Autodesk Fusion 360 part; units mm, degrees
(part 14 of 18)
  line L10793 (174.975, -141.859) -> (174.627, -141.389)
  line L10794 (21.5489, -130.12) -> (21.157, -130.566)
  line L10795 (180.123, -127.511) -> (179.548, -127.659)
  line L10796 (151.541, -210.058) -> (151.739, -210.617)
  line L10797 (186.581, -167.69) -> (187.084, -167.374)
  line L10798 (20.7955, -131.037) -> (20.466, -131.531)
  line L10799 (191.021, -160.387) -> (191.032, -159.95)
  line L10800 (164.561, -215.211) -> (164.044, -215.484)
  line L10801 (188.022, -166.647) -> (188.453, -166.238)
  line L10802 (27.2963, -127.329) -> (26.7068, -127.4)
  line L10803 (119.128, -104.03) -> (119.671, -104.244)
  line L10804 (190.153, -163.819) -> (190.391, -163.276)
  line L10805 (182.046, -168.905) -> (182.639, -168.887)
  line L10806 (109.882, -105.953) -> (110.32, -105.567)
  line L10807 (176.187, -143.121) -> (175.756, -142.727)
  line L10808 (187.565, -167.026) -> (188.022, -166.647)
  line L10809 (188.856, -165.801) -> (189.229, -165.339)
  line L10810 (19.1587, -135.438) -> (19.1245, -136.031)
  line L10811 (182.266, -127.202) -> (182.85, -127.233)
  line L10812 (155.018, -214.739) -> (155.518, -215.058)
  line L10813 (175.549, -130.12) -> (175.157, -130.566)
  line L10814 (186.581, -143.99) -> (187.084, -143.674)
  line L10815 (187.059, -143.805) -> (186.561, -144.111)
  line L10816 (189.229, -165.339) -> (189.57, -164.853)
  line L10817 (173.159, -134.71) -> (173.277, -134.137)
  line L10818 (181.682, -127.209) -> (182.266, -127.202)
  line L10819 (154.539, -214.387) -> (155.018, -214.739)
  line L10820 (166.856, -213.201) -> (167.229, -212.739)
  line L10821 (187.441, -129.079) -> (186.954, -128.74)
  line L10822 (173.909, -132.579) -> (173.683, -133.129)
  line L10823 (189.57, -164.853) -> (189.879, -164.346)
  line L10824 (173.078, -135.288) -> (173.159, -134.71)
  line L10825 (188.938, -130.349) -> (189.304, -130.804)
  line L10826 (154.085, -214.005) -> (154.539, -214.387)
  line L10827 (166.453, -213.638) -> (166.856, -213.201)
  line L10828 (168.389, -210.93) -> (168.14, -211.459)
  line L10829 (184.243, -127.561) -> (183.663, -127.437)
  line L10830 (187.536, -143.468) -> (187.059, -143.805)
  line L10831 (19.1297, -136.625) -> (19.1742, -137.217)
  line L10832 (188.543, -129.918) -> (188.938, -130.349)
  line L10833 (173.777, -139.859) -> (173.562, -139.316)
  line L10834 (36.5439, -133.335) -> (36.3321, -132.78)
  line L10835 (168.602, -210.386) -> (168.389, -210.93)
  line L10836 (190.084, -155.94) -> (189.801, -155.418)
  line L10837 (180.276, -145.022) -> (180.861, -145.122)
  line L10838 (174.55, -141.101) -> (174.888, -141.589)
  line L10839 (188.121, -129.514) -> (188.543, -129.918)
  line L10840 (110.32, -105.567) -> (110.783, -105.21)
  line L10841 (36.7185, -133.902) -> (36.5439, -133.335)
  line L10842 (162.963, -215.927) -> (162.404, -216.096)
  line L10843 (189.801, -155.418) -> (189.483, -154.917)
  line L10844 (177.518, -143.958) -> (178.039, -144.243)
  line L10845 (174.466, -131.531) -> (174.17, -132.046)
  line L10846 (36.8551, -134.48) -> (36.7185, -133.902)
  line L10847 (163.511, -215.723) -> (162.963, -215.927)
  line L10848 (190.391, -163.276) -> (190.594, -162.717)
  line L10849 (185.518, -168.217) -> (186.059, -167.971)
  line L10850 (188.342, -129.852) -> (187.904, -129.451)
  line L10851 (176.417, -129.31) -> (175.97, -129.701)
  line L10852 (158.861, -216.222) -> (159.452, -216.283)
  line L10853 (173.033, -136.031) -> (173.035, -135.871)
  line L10854 (164.044, -215.484) -> (163.511, -215.723)
  line L10855 (190.594, -162.717) -> (190.758, -162.147)
  line L10856 (186.059, -167.971) -> (186.581, -167.69)
  line L10857 (174.727, -130.969) -> (175.084, -130.506)
  line L10858 (184.963, -144.727) -> (185.518, -144.517)
  line L10859 (158.276, -216.122) -> (158.861, -216.222)
  line L10860 (107.622, -109.322) -> (107.848, -108.783)
  line L10861 (177.121, -143.823) -> (176.643, -143.487)
  line L10862 (190.758, -162.147) -> (190.885, -161.567)
  line L10863 (183.816, -168.734) -> (184.395, -168.6)
  line L10864 (174.402, -131.454) -> (174.727, -130.969)
  line L10865 (176.783, -128.91) -> (177.268, -128.584)
  line L10866 (160.639, -216.287) -> (161.23, -216.23)
  line L10867 (107.848, -108.783) -> (108.108, -108.26)
  line L10868 (186.954, -128.74) -> (186.446, -128.433)
  line L10869 (187.99, -143.101) -> (187.536, -143.468)
  line L10870 (184.395, -168.6) -> (184.963, -168.427)
  line L10871 (175.882, -129.653) -> (176.32, -129.267)
  line L10872 (176.32, -129.267) -> (176.783, -128.91)
  line L10873 (160.046, -216.305) -> (160.639, -216.287)
  line L10874 (161.816, -216.134) -> (162.395, -216)
  line L10875 (185.373, -127.924) -> (184.814, -127.724)
  line L10876 (173.683, -133.129) -> (173.495, -133.692)
  line L10877 (184.963, -168.427) -> (185.518, -168.217)
  line L10878 (175.469, -130.066) -> (175.882, -129.653)
  line L10879 (184.005, -127.408) -> (184.571, -127.551)
  line L10880 (159.452, -216.283) -> (160.046, -216.305)
  line L10881 (161.23, -216.23) -> (161.816, -216.134)
  line L10882 (168.218, -203.397) -> (168.456, -203.931)
  line L10883 (117.43, -103.602) -> (118.005, -103.708)
  line L10884 (186.561, -144.111) -> (186.044, -144.384)
  line L10885 (175.084, -130.506) -> (175.469, -130.066)
  line L10886 (183.43, -127.302) -> (184.005, -127.408)
  line L10887 (173.382, -138.76) -> (173.238, -138.193)
  line L10888 (167.879, -211.746) -> (168.153, -211.219)
  line L10889 (167.946, -202.88) -> (168.218, -203.397)
  line L10890 (185.918, -151.861) -> (185.373, -151.624)
  line L10891 (175.257, -142.054) -> (175.657, -142.493)
  line L10892 (182.85, -127.233) -> (183.43, -127.302)
  line L10893 (179.548, -127.659) -> (178.985, -127.846)
  line L10894 (167.57, -212.253) -> (167.879, -211.746)
  line L10895 (167.544, -212.463) -> (167.199, -212.934)
  line L10896 (185.373, -151.624) -> (184.814, -151.424)
  line L10897 (182.046, -145.205) -> (182.639, -145.187)
  line L10898 (176.539, -143.287) -> (177.018, -143.639)
  line L10899 (174.17, -132.046) -> (173.909, -132.579)
  line L10900 (167.229, -212.739) -> (167.57, -212.253)
  line L10901 (167.858, -211.97) -> (167.544, -212.463)
  line L10902 (190.719, -157.602) -> (190.544, -157.035)
  line L10903 (177.018, -167.339) -> (177.518, -167.658)
  line L10904 (190.084, -132.24) -> (189.801, -131.718)
  line L10905 (191.012, -135.657) -> (190.953, -135.066)
  line L10906 (164.581, -215.09) -> (165.084, -214.774)
  line L10907 (173.061, -137.039) -> (173.029, -136.455)
  line L10908 (168.14, -211.459) -> (167.858, -211.97)
  line L10909 (190.544, -157.035) -> (190.332, -156.48)
  line L10910 (177.518, -167.658) -> (178.039, -167.943)
  line L10911 (179.386, -127.609) -> (179.949, -127.454)
  line L10912 (164.059, -215.371) -> (164.581, -215.09)
  line L10913 (108.108, -108.26) -> (108.402, -107.754)
  line L10914 (178.138, -144.398) -> (177.62, -144.127)
  line L10915 (190.332, -156.48) -> (190.084, -155.94)
  line L10916 (175.657, -166.193) -> (176.085, -166.605)
  line L10917 (178.834, -127.801) -> (179.386, -127.609)
  line L10918 (173.432, -133.574) -> (173.622, -133.022)
  line L10919 (166.022, -214.047) -> (166.453, -213.638)
  line L10920 (173.495, -133.692) -> (173.344, -134.266)
  line L10921 (113.949, -103.754) -> (114.521, -103.635)
  line L10922 (188.823, -142.282) -> (188.42, -142.705)
  line L10923 (176.085, -166.605) -> (176.539, -166.987)
  line L10924 (181.099, -127.253) -> (181.682, -127.209)
  line L10925 (173.277, -134.137) -> (173.432, -133.574)
  line L10926 (165.565, -214.426) -> (166.022, -214.047)
  line L10927 (156.039, -215.343) -> (156.578, -215.593)
  line L10928 (112.834, -104.101) -> (113.386, -103.909)
  line L10929 (115.682, -103.509) -> (116.266, -103.502)
  line L10930 (176.539, -166.987) -> (177.018, -167.339)
  line L10931 (180.521, -127.335) -> (181.099, -127.253)
  line L10932 (178.295, -128.028) -> (178.834, -127.801)
  line L10933 (165.084, -214.774) -> (165.565, -214.426)
  line L10934 (155.518, -215.058) -> (156.039, -215.343)
  line L10935 (161.43, -198.402) -> (162.005, -198.508)
  line L10936 (112.295, -104.328) -> (112.834, -104.101)
  line L10937 (184.963, -144.827) -> (184.404, -144.996)
  line L10938 (179.949, -127.454) -> (180.521, -127.335)
  line L10939 (177.772, -128.289) -> (178.295, -128.028)
  line L10940 (173.131, -137.619) -> (173.061, -137.039)
  line L10941 (163.518, -215.617) -> (164.059, -215.371)
  line L10942 (160.85, -198.333) -> (161.43, -198.402)
  line L10943 (180.123, -151.211) -> (179.548, -151.359)
  line L10944 (189.879, -140.646) -> (190.153, -140.119)
  line L10945 (176.085, -142.905) -> (176.539, -143.287)
  line L10946 (177.268, -128.584) -> (177.772, -128.289)
  line L10947 (110.783, -105.21) -> (111.268, -104.884)
  line L10948 (162.963, -215.827) -> (163.518, -215.617)
  line L10949 (168.827, -205.038) -> (168.957, -205.608)
  line L10950 (179.548, -151.359) -> (178.985, -151.546)
  line L10951 (183.816, -145.034) -> (184.395, -144.9)
  line L10952 (178.434, -128.069) -> (177.9, -128.329)
  line L10953 (175.657, -142.493) -> (176.085, -142.905)
  line L10954 (111.268, -104.884) -> (111.772, -104.589)
  line L10955 (162.395, -216) -> (162.963, -215.827)
  line L10956 (168.659, -204.478) -> (168.827, -205.038)
  line L10957 (187.441, -152.779) -> (186.954, -152.44)
  line L10958 (151.848, -203.583) -> (152.108, -203.06)
  line L10959 (176.889, -128.951) -> (176.417, -129.31)
  line L10960 (168.391, -210.676) -> (168.594, -210.117)
  line L10961 (173.238, -138.193) -> (173.131, -137.619)
  line L10962 (168.456, -203.931) -> (168.659, -204.478)
  line L10963 (186.954, -152.44) -> (186.446, -152.133)
  line L10964 (151.622, -204.122) -> (151.848, -203.583)
  line L10965 (185.128, -127.73) -> (185.671, -127.944)
  line L10966 (108.727, -107.269) -> (109.084, -106.806)
  line L10967 (168.153, -211.219) -> (168.391, -210.676)
  line L10968 (175.157, -130.566) -> (174.795, -131.037)
  line L10969 (179.22, -144.837) -> (178.672, -144.635)
  line L10970 (186.446, -152.133) -> (185.918, -151.861)
  line L10971 (152.727, -202.069) -> (153.084, -201.606)
  line L10972 (184.571, -127.551) -> (185.128, -127.73)
  line L10973 (19.6834, -133.129) -> (19.495, -133.692)
  line L10974 (37.0318, -136.25) -> (37.0121, -135.657)
  line L10975 (108.402, -107.754) -> (108.727, -107.269)
  line L10976 (116.266, -103.502) -> (116.85, -103.533)
  line L10977 (189.544, -141.363) -> (189.199, -141.834)
  line L10978 (152.402, -202.554) -> (152.727, -202.069)
  line L10979 (186.711, -128.476) -> (187.203, -128.792)
  line L10980 (19.9088, -132.579) -> (19.6834, -133.129)
  line L10981 (19.6834, -62.0285) -> (19.495, -62.5917)
  line L10982 (151.974, -211.163) -> (152.245, -211.691)
  line L10983 (185.918, -128.161) -> (185.373, -127.924)
  line L10984 (152.108, -203.06) -> (152.402, -202.554)
  line L10985 (186.199, -128.194) -> (186.711, -128.476)
  line L10986 (174.108, -131.96) -> (174.402, -131.454)
  line L10987 (168.594, -210.117) -> (168.758, -209.547)
  line L10988 (151.739, -210.617) -> (151.974, -211.163)
  line L10989 (153.469, -201.166) -> (153.882, -200.753)
  line L10990 (188.022, -142.947) -> (188.453, -142.538)
  line L10991 (183.258, -145.223) -> (182.677, -145.28)
  line L10992 (185.671, -127.944) -> (186.199, -128.194)
  line L10993 (173.848, -132.483) -> (174.108, -131.96)
  line L10994 (173.029, -136.455) -> (173.033, -136.031)
  line L10995 (157.699, -215.983) -> (158.276, -216.122)
  line L10996 (153.084, -201.606) -> (153.469, -201.166)
  line L10997 (178.985, -151.546) -> (178.434, -151.769)
  line L10998 (187.565, -143.326) -> (188.022, -142.947)
  line L10999 (177.018, -143.639) -> (177.518, -143.958)
  line L11000 (173.622, -133.022) -> (173.848, -132.483)
  line L11001 (120.199, -104.494) -> (120.711, -104.776)
  line L11002 (157.132, -215.807) -> (157.699, -215.983)
  line L11003 (163.128, -198.83) -> (163.671, -199.044)
  line L11004 (178.434, -151.769) -> (177.9, -152.029)
  line L11005 (187.084, -143.674) -> (187.565, -143.326)
  line L11006 (183.23, -145.13) -> (183.816, -145.034)
  line L11007 (174.888, -141.589) -> (175.257, -142.054)
  line L11008 (118.571, -103.851) -> (119.128, -104.03)
  line L11009 (156.578, -215.593) -> (157.132, -215.807)
  line L11010 (162.571, -198.651) -> (163.128, -198.83)
  line L11011 (181.889, -150.997) -> (181.296, -151.029)
  line L11012 (158.521, -198.435) -> (159.099, -198.353)
  line L11013 (188.856, -142.101) -> (189.229, -141.639)
  line L11014 (36.084, -132.24) -> (35.8006, -131.718)
  line L11015 (173.562, -139.316) -> (173.382, -138.76)
  line L11016 (162.005, -198.508) -> (162.571, -198.651)
  line L11017 (181.296, -151.029) -> (180.707, -151.1)
  line L11018 (157.949, -198.554) -> (158.521, -198.435)
  line L11019 (189.641, -131.281) -> (189.946, -131.78)
  line L11020 (190.544, -133.335) -> (190.332, -132.78)
  line L11021 (36.3321, -132.78) -> (36.084, -132.24)
  line L11022 (180.927, -145.227) -> (180.35, -145.134)
  line L11023 (180.707, -151.1) -> (180.123, -151.211)
  line L11024 (160.266, -198.302) -> (160.85, -198.333)
  line L11025 (189.304, -130.804) -> (189.641, -131.281)
  line L11026 (23.3845, -128.623) -> (22.8893, -128.951)
  line L11027 (35.1334, -130.737) -> (34.7525, -130.281)
  line L11028 (186.446, -128.433) -> (185.918, -128.161)
  line L11029 (190.14, -140.359) -> (189.858, -140.87)
  line L11030 (159.682, -198.309) -> (160.266, -198.302)
  line L11031 (190.456, -132.831) -> (190.659, -133.378)
  line L11032 (23.9003, -128.329) -> (23.3845, -128.623)
  line L11033 (35.4833, -131.217) -> (35.1334, -130.737)
  line L11034 (151.131, -208.719) -> (151.061, -208.139)
  line L11035 (173.232, -134.849) -> (173.159, -135.438)
  line L11036 (116.85, -103.533) -> (117.43, -103.602)
  line L11037 (159.099, -198.353) -> (159.682, -198.309)
  line L11038 (35.8006, -131.718) -> (35.4833, -131.217)
  line L11039 (190.218, -132.297) -> (190.456, -132.831)
  line L11040 (19.232, -134.849) -> (19.1587, -135.438)
  line L11041 (174.888, -165.289) -> (175.257, -165.754)
  line L11042 (115.099, -103.553) -> (115.682, -103.509)
  line L11043 (151.238, -209.293) -> (151.131, -208.719)
  line L11044 (181.509, -145.282) -> (180.927, -145.227)
  line L11045 (189.946, -131.78) -> (190.218, -132.297)
  line L11046 (19.3443, -134.266) -> (19.232, -134.849)
  line L11047 (173.035, -135.871) -> (173.078, -135.288)
  line L11048 (152.888, -212.689) -> (153.257, -213.154)
  line L11049 (175.257, -165.754) -> (175.657, -166.193)
  line L11050 (183.075, -151.051) -> (182.483, -151.004)
  line L11051 (181.452, -145.183) -> (182.046, -145.205)
  line L11052 (178.039, -144.243) -> (178.578, -144.493)
  line L11053 (19.495, -133.692) -> (19.3443, -134.266)
  line L11054 (189.229, -141.639) -> (189.57, -141.153)
  line L11055 (152.55, -212.201) -> (152.888, -212.689)
  line L11056 (154.783, -200.01) -> (155.268, -199.684)
  line L11057 (182.483, -151.004) -> (181.889, -150.997)
  line L11058 (189.57, -141.153) -> (189.879, -140.646)
  line L11059 (177.9, -128.329) -> (177.385, -128.623)
  line L11060 (174.245, -140.591) -> (174.55, -141.101)
  line L11061 (111.772, -104.589) -> (112.295, -104.328)
  line L11062 (152.245, -211.691) -> (152.55, -212.201)
  line L11063 (154.32, -200.367) -> (154.783, -200.01)
  line L11064 (184.814, -151.424) -> (184.243, -151.261)
  line L11065 (166.543, -201.018) -> (166.938, -201.449)
  line L11066 (177.385, -128.623) -> (176.889, -128.951)
  line L11067 (190.332, -132.78) -> (190.084, -132.24)
  line L11068 (31.9179, -128.161) -> (31.3734, -127.924)
  line L11069 (174.028, -140.387) -> (173.777, -139.859)
  line L11070 (153.882, -200.753) -> (154.32, -200.367)
  line L11071 (184.243, -151.261) -> (183.663, -151.137)
  line L11072 (166.121, -200.614) -> (166.543, -201.018)
  line L11073 (188.753, -130.281) -> (188.342, -129.852)
  line L11074 (109.084, -106.806) -> (109.469, -106.366)
  line L11075 (32.4456, -128.433) -> (31.9179, -128.161)
  line L11076 (173.344, -134.266) -> (173.232, -134.849)
  line L11077 (182.677, -145.28) -> (182.093, -145.3)
  line L11078 (183.663, -151.137) -> (183.075, -151.051)
  line L11079 (167.641, -202.381) -> (167.946, -202.88)
  line L11080 (184.395, -144.9) -> (184.963, -144.727)
  line L11081 (29.075, -127.351) -> (28.483, -127.304)
  line L11082 (30.2432, -127.561) -> (29.6626, -127.437)
  line L11083 (114.521, -103.635) -> (115.099, -103.553)
  line L11084 (189.858, -140.87) -> (189.544, -141.363)
  line L11085 (167.304, -201.904) -> (167.641, -202.381)
  line L11086 (190.922, -138.162) -> (190.781, -138.729)
  line L11087 (29.6626, -127.437) -> (29.075, -127.351)
  line L11088 (30.8143, -127.724) -> (30.2432, -127.561)
  line L11089 (153.756, -213.827) -> (153.351, -213.406)
  line L11090 (173.159, -135.438) -> (173.124, -136.031)
  line L11091 (180.861, -145.122) -> (181.452, -145.183)
  line L11092 (166.938, -201.449) -> (167.304, -201.904)
  line L11093 (191.027, -137.588) -> (190.922, -138.162)
  line L11094 (21.9695, -129.701) -> (21.5489, -130.12)
  line L11095 (31.3734, -127.924) -> (30.8143, -127.724)
  line L11096 (154.187, -214.221) -> (153.756, -213.827)
  line L11097 (182.639, -168.887) -> (183.23, -168.83)
  line L11098 (186.059, -144.271) -> (186.581, -143.99)
  line L11099 (179.78, -145.004) -> (179.22, -144.837)
  line L11100 (191.095, -137.007) -> (191.027, -137.588)
  line L11101 (22.417, -129.31) -> (21.9695, -129.701)
  line L11102 (173.258, -137.805) -> (173.38, -138.386)
  line L11103 (151.033, -207.131) -> (151.035, -206.971)
  line L11104 (183.23, -168.83) -> (183.816, -168.734)
  line L11105 (188.342, -153.552) -> (187.904, -153.151)
  line L11106 (179.132, -144.707) -> (179.699, -144.883)
  line L11107 (22.8893, -128.951) -> (22.417, -129.31)
  line L11108 (151.029, -207.555) -> (151.033, -207.131)
  line L11109 (173.974, -163.763) -> (174.245, -164.291)
  line L11110 (187.904, -153.151) -> (187.441, -152.779)
  line L11111 (190.885, -137.867) -> (190.972, -137.279)
  line L11112 (191.051, -135.084) -> (191.108, -135.666)
  line L11113 (173.739, -139.517) -> (173.974, -140.063)
  line L11114 (119.671, -104.244) -> (120.199, -104.494)
  line L11115 (151.061, -208.139) -> (151.029, -207.555)
  line L11116 (174.245, -164.291) -> (174.55, -164.801)
  line L11117 (189.483, -154.917) -> (189.133, -154.437)
  line L11118 (169.027, -208.688) -> (168.922, -209.262)
  line L11119 (190.957, -134.508) -> (191.051, -135.084)
  line L11120 (109.469, -106.366) -> (109.882, -105.953)
  line L11121 (26.1233, -127.511) -> (25.5484, -127.659)
  line L11122 (174.627, -141.389) -> (174.311, -140.898)
  line L11123 (174.55, -164.801) -> (174.888, -165.289)
  line L11124 (189.133, -154.437) -> (188.753, -153.981)
  line L11125 (169.095, -208.107) -> (169.027, -208.688)
  line L11126 (190.827, -133.938) -> (190.957, -134.508)
  line L11127 (191.032, -136.25) -> (191.012, -135.657)
  line L11128 (26.7068, -127.4) -> (26.1233, -127.511)
  line L11129 (190.719, -133.902) -> (190.544, -133.335)
  line L11130 (184.404, -144.996) -> (183.835, -145.128)
  line L11131 (188.753, -153.981) -> (188.342, -153.552)
  line L11132 (168.781, -209.829) -> (168.602, -210.386)
  line L11133 (190.659, -133.378) -> (190.827, -133.938)
  line L11134 (34.3423, -129.852) -> (33.9045, -129.451)
  line L11135 (24.4345, -128.069) -> (23.9003, -128.329)
  line L11136 (190.855, -134.48) -> (190.719, -133.902)
  line L11137 (173.124, -136.031) -> (173.13, -136.625)
  line L11138 (189.199, -141.834) -> (188.823, -142.282)
  line L11139 (168.922, -209.262) -> (168.781, -209.829)
  line L11140 (190.389, -139.83) -> (190.14, -140.359)
  line L11141 (34.7525, -130.281) -> (34.3423, -129.852)
  line L11142 (24.9847, -127.846) -> (24.4345, -128.069)
  line L11143 (158.927, -216.327) -> (158.35, -216.234)
  line L11144 (173.13, -136.625) -> (173.174, -137.217)
  line L11145 (94.6766, -97.8801) -> (94.0926, -97.9)
  line L11146 (95.2302, -97.7304) -> (95.8162, -97.6345)
  line L11147 (103.027, -90.1877) -> (102.922, -90.7625)
  line L11148 (115.099, -79.8529) -> (115.682, -79.8086)
  line L11149 (120.711, -81.0764) -> (121.203, -81.3917)
  line L11150 (85.495, -86.2917) -> (85.3443, -86.866)
  line L11151 (93.2963, -79.9291) -> (92.7068, -80.0004)
  line L11152 (89.1214, -96.4227) -> (88.643, -96.0871)
  line L11153 (85.0347, -88.471) -> (85.078, -87.8883)
  line L11154 (88.539, -95.8873) -> (89.0175, -96.2389)
  line L11155 (93.0994, -79.8529) -> (93.682, -79.8086)
  line L11156 (95.8162, -97.6345) -> (96.3945, -97.4999)
  line L11157 (89.0175, -96.2389) -> (89.5183, -96.5579)
  line L11158 (91.7803, -97.6038) -> (91.2202, -97.4373)
  line L11159 (85.1742, -89.8171) -> (85.2578, -90.405)
  line L11160 (85.5618, -91.9156) -> (85.3817, -91.3597)
  line L11161 (102.594, -91.6172) -> (102.758, -91.0467)
  line L11162 (36.8551, -110.78) -> (36.7185, -110.202)
  line L11163 (124.456, -85.4305) -> (124.659, -85.9784)
  line L11164 (102.827, -86.5382) -> (102.957, -87.1077)
  line L11165 (89.5183, -96.5579) -> (90.0392, -96.8431)
  line L11166 (19.1297, -112.925) -> (19.1742, -113.517)
  line L11167 (36.3914, -115.876) -> (36.5935, -115.317)
  line L11168 (95.8346, -97.7276) -> (95.2581, -97.8226)
  line L11169 (88.1873, -95.7214) -> (87.7561, -95.327)
  line L11170 (102.084, -84.8403) -> (101.801, -84.3185)
  line L11171 (86.6274, -93.989) -> (86.3113, -93.4975)
  line L11172 (25.5484, -103.959) -> (24.9847, -104.146)
  line L11173 (119.671, -80.5443) -> (120.199, -80.7936)
  line L11174 (19.1245, -112.331) -> (19.1297, -112.925)
  line L11175 (100.121, -82.114) -> (100.543, -82.518)
  line L11176 (36.5439, -109.635) -> (36.3321, -109.08)
  line L11177 (85.0291, -89.0553) -> (85.0332, -88.6312)
  line L11178 (88.7829, -81.5099) -> (89.2676, -81.1835)
  line L11179 (121.203, -81.3917) -> (121.673, -81.738)
  line L11180 (102.544, -85.9345) -> (102.332, -85.3798)
  line L11181 (121.673, -81.738) -> (122.121, -82.114)
  line L11182 (93.5085, -97.8821) -> (92.9269, -97.8266)
  line L11183 (87.157, -83.166) -> (86.7955, -83.6371)
  line L11184 (97.5109, -97.2231) -> (96.9634, -97.4273)
  line L11185 (85.2379, -90.7934) -> (85.1309, -90.2189)
  line L11186 (103.108, -88.266) -> (103.127, -88.85)
  line L11187 (88.417, -81.9104) -> (87.9695, -82.3007)
  line L11188 (112.834, -80.4011) -> (113.386, -80.2094)
  line L11189 (86.3113, -93.4975) -> (86.0276, -92.9867)
  line L11190 (92.1233, -80.1107) -> (91.5484, -80.2593)
  line L11191 (122.543, -82.518) -> (122.938, -82.9485)
  line L11192 (27.2963, -103.629) -> (26.7068, -103.7)
  line L11193 (88.3203, -81.8668) -> (88.7829, -81.5099)
  line L11194 (98.0585, -96.8711) -> (98.5813, -96.5896)
  line L11195 (119.128, -80.3297) -> (119.671, -80.5443)
  line L11196 (113.949, -80.0538) -> (114.521, -79.9348)
  line L11197 (37.0121, -111.957) -> (36.9531, -111.366)
  line L11198 (101.133, -83.3368) -> (100.753, -82.8812)
  line L11199 (23.9003, -104.629) -> (23.3845, -104.923)
  line L11200 (92.5208, -79.9348) -> (93.0994, -79.8529)
  line L11201 (100.453, -95.1378) -> (100.856, -94.7014)
  line L11202 (118.571, -80.1506) -> (119.128, -80.3297)
  line L11203 (91.6987, -97.4835) -> (92.2761, -97.6221)
  line L11204 (31.9179, -104.461) -> (31.3734, -104.224)
  line L11205 (125.108, -88.266) -> (125.127, -88.85)
  line L11206 (101.641, -83.8813) -> (101.946, -84.3798)
  line L11207 (90.4345, -80.6692) -> (89.9003, -80.9286)
  line L11208 (20.466, -107.831) -> (20.17, -108.346)
  line L11209 (27.8893, -103.597) -> (27.2963, -103.629)
  line L11210 (36.7582, -114.747) -> (36.8847, -114.167)
  line L11211 (94.6391, -97.7873) -> (95.2302, -97.7304)
  line L11212 (85.6834, -85.7285) -> (85.495, -86.2917)
  line L11213 (29.6626, -103.737) -> (29.075, -103.651)
  line L11214 (101.946, -84.3798) -> (102.218, -84.8969)
  line L11215 (102.758, -91.0467) -> (102.885, -90.4665)
  line L11216 (21.9695, -106.001) -> (21.5489, -106.42)
  line L11217 (91.5484, -80.2593) -> (90.9847, -80.4458)
  line L11218 (90.138, -96.9979) -> (89.6204, -96.7267)
  line L11219 (97.3734, -80.5239) -> (96.8143, -80.3237)
  line L11220 (30.8143, -104.024) -> (30.2432, -103.861)
  line L11221 (115.682, -79.8086) -> (116.266, -79.802)
  line L11222 (98.1995, -80.7936) -> (98.7108, -81.0764)
  line L11223 (102.957, -87.1077) -> (103.051, -87.6844)
  line L11224 (102.391, -92.1756) -> (102.594, -91.6172)
  line L11225 (85.3443, -86.866) -> (85.2321, -87.4491)
  line L11226 (102.972, -89.8793) -> (103.021, -89.2874)
  line L11227 (35.4833, -107.517) -> (35.1334, -107.037)
  line L11228 (96.9627, -97.3272) -> (97.5182, -97.1173)
  line L11229 (87.8816, -82.2528) -> (88.3203, -81.8668)
  line L11230 (21.5489, -106.42) -> (21.157, -106.866)
  line L11231 (30.2432, -103.861) -> (29.6626, -103.737)
  line L11232 (86.1085, -84.5595) -> (86.402, -84.0542)
  line L11233 (103.125, -89.0237) -> (103.095, -89.6073)
  line L11234 (90.672, -97.2351) -> (90.138, -96.9979)
  line L11235 (95.2581, -97.8226) -> (94.6766, -97.8801)
  line L11236 (101.304, -83.4036) -> (101.641, -83.8813)
  line L11237 (102.922, -90.7625) -> (102.781, -91.3293)
  line L11238 (98.954, -81.3397) -> (98.4456, -81.033)
  line L11239 (36.9725, -113.579) -> (37.0211, -112.987)
  line L11240 (111.772, -80.8892) -> (112.295, -80.628)
  line L11241 (86.2446, -93.1915) -> (86.5495, -93.701)
  line L11242 (96.8143, -80.3237) -> (96.2432, -80.161)
  line L11243 (107.848, -85.0827) -> (108.108, -84.5595)
  line L11244 (32.4456, -104.733) -> (31.9179, -104.461)
  line L11245 (98.4456, -81.033) -> (97.9179, -80.7606)
  line L11246 (87.2572, -94.6539) -> (87.6569, -95.0931)
  line L11247 (94.8498, -79.8331) -> (95.4301, -79.9018)
  line L11248 (124.218, -84.8969) -> (124.456, -85.4305)
  line L11249 (94.483, -79.9042) -> (93.8893, -79.897)
  line L11250 (95.075, -79.9508) -> (94.483, -79.9042)
  line L11251 (101.879, -93.246) -> (102.153, -92.7193)
  line L11252 (86.402, -84.0542) -> (86.7274, -83.569)
  line L11253 (94.0926, -97.9) -> (93.5085, -97.8821)
  line L11254 (100.753, -82.8812) -> (100.342, -82.4519)
  line L11255 (107.159, -87.3096) -> (107.277, -86.7373)
  line L11256 (86.7274, -83.569) -> (87.0836, -83.1057)
  line L11257 (107.078, -87.8883) -> (107.159, -87.3096)
  line L11258 (96.0047, -80.0077) -> (96.5713, -80.1506)
  line L11259 (100.022, -95.5465) -> (100.453, -95.1378)
  line L11260 (85.1587, -88.0384) -> (85.1245, -88.6312)
  line L11261 (101.544, -93.963) -> (101.199, -94.4342)
  line L11262 (100.938, -82.9485) -> (101.304, -83.4036)
  line L11263 (102.389, -92.4297) -> (102.14, -92.9586)
  line L11264 (92.9269, -97.8266) -> (92.35, -97.7337)
  line L11265 (91.9488, -80.0538) -> (92.5208, -79.9348)
  line L11266 (36.084, -108.54) -> (35.8006, -108.018)
  line L11267 (85.1297, -89.225) -> (85.1742, -89.8171)
  line L11268 (24.9847, -104.146) -> (24.4345, -104.369)
  line L11269 (29.075, -103.651) -> (28.483, -103.604)
  line L11270 (114.521, -79.9348) -> (115.099, -79.8529)
  line L11271 (86.8876, -94.1892) -> (87.2572, -94.6539)
  line L11272 (20.7955, -107.337) -> (20.466, -107.831)
  line L11273 (86.0276, -92.9867) -> (85.7774, -92.4587)
  line L11274 (90.0392, -96.8431) -> (90.5778, -97.0931)
  line L11275 (86.7955, -83.6371) -> (86.466, -84.1311)
  line L11276 (31.3734, -104.224) -> (30.8143, -104.024)
  line L11277 (102.332, -85.3798) -> (102.084, -84.8403)
  line L11278 (103.095, -89.6073) -> (103.027, -90.1877)
  line L11279 (102.885, -90.4665) -> (102.972, -89.8793)
  line L11280 (102.153, -92.7193) -> (102.391, -92.1756)
  line L11281 (123.946, -84.3798) -> (124.218, -84.8969)
  line L11282 (107.432, -86.1738) -> (107.622, -85.6215)
  line L11283 (35.8785, -116.946) -> (36.1527, -116.419)
  line L11284 (85.1309, -90.2189) -> (85.0612, -89.6388)
  line L11285 (102.719, -86.5021) -> (102.544, -85.9345)
  line L11286 (87.3513, -94.9056) -> (86.9746, -94.459)
  line L11287 (87.5489, -82.7199) -> (87.157, -83.166)
  line L11288 (88.8893, -81.5505) -> (88.417, -81.9104)
  line L11289 (102.659, -85.9784) -> (102.827, -86.5382)
  line L11290 (122.938, -82.9485) -> (123.304, -83.4036)
  line L11291 (103.051, -87.6844) -> (103.108, -88.266)
  line L11292 (98.5813, -96.5896) -> (99.0844, -96.274)
  line L11293 (95.4301, -79.9018) -> (96.0047, -80.0077)
  line L11294 (101.801, -84.3185) -> (101.483, -83.8165)
  line L11295 (34.7525, -106.581) -> (34.3423, -106.152)
  line L11296 (19.1587, -111.738) -> (19.1245, -112.331)
  line L11297 (91.2202, -97.4373) -> (90.672, -97.2351)
  line L11298 (112.295, -80.628) -> (112.834, -80.4011)
  line L11299 (35.57, -117.453) -> (35.8785, -116.946)
  line L11300 (99.2028, -81.3917) -> (99.6734, -81.738)
  line L11301 (99.6734, -81.738) -> (100.121, -82.114)
  line L11302 (124.827, -86.5382) -> (124.957, -87.1077)
  line L11303 (86.9746, -94.459) -> (86.6274, -93.989)
  line L11304 (99.0587, -96.4054) -> (98.5607, -96.7111)
  line L11305 (109.469, -82.6664) -> (109.882, -82.2528)
  line L11306 (102.14, -92.9586) -> (101.858, -93.4704)
  line L11307 (23.3845, -104.923) -> (22.8893, -105.251)
  line L11308 (96.5713, -80.1506) -> (97.1275, -80.3297)
  line L11309 (36.8847, -114.167) -> (36.9725, -113.579)
  line L11310 (123.641, -83.8813) -> (123.946, -84.3798)
  line L11311 (34.3423, -106.152) -> (33.9045, -105.751)
  line L11312 (98.7108, -81.0764) -> (99.2028, -81.3917)
  line L11313 (99.5358, -96.0681) -> (99.0587, -96.4054)
  line L11314 (85.1589, -87.3096) -> (85.2769, -86.7373)
  line L11315 (107.622, -85.6215) -> (107.848, -85.0827)
  line L11316 (85.2578, -90.405) -> (85.3803, -90.9861)
  line L11317 (28.483, -103.604) -> (27.8893, -103.597)
  line L11318 (102.218, -84.8969) -> (102.456, -85.4305)
  line L11319 (124.659, -85.9784) -> (124.827, -86.5382)
  line L11320 (85.7392, -92.1175) -> (85.9741, -92.6629)
  line L11321 (123.304, -83.4036) -> (123.641, -83.8813)
  line L11322 (92.2761, -97.6221) -> (92.8615, -97.7221)
  line L11323 (36.3321, -109.08) -> (36.084, -108.54)
  line L11324 (87.0836, -83.1057) -> (87.4688, -82.6664)
  line L11325 (92.7068, -80.0004) -> (92.1233, -80.1107)
  line L11326 (103.032, -88.85) -> (103.012, -88.2565)
  line L11327 (97.1275, -80.3297) -> (97.671, -80.5443)
  line L11328 (92.8615, -97.7221) -> (93.4521, -97.7832)
  line L11329 (36.7185, -110.202) -> (36.5439, -109.635)
  line L11330 (90.5778, -97.0931) -> (91.1318, -97.3069)
  line L11331 (101.483, -83.8165) -> (101.133, -83.3368)
  line L11332 (86.5495, -93.701) -> (86.8876, -94.1892)
  line L11333 (101.57, -93.7534) -> (101.879, -93.246)
  line L11334 (87.4688, -82.6664) -> (87.8816, -82.2528)
  line L11335 (85.9741, -92.6629) -> (86.2446, -93.1915)
  line L11336 (87.9695, -82.3007) -> (87.5489, -82.7199)
  line L11337 (122.121, -82.114) -> (122.543, -82.518)
  line L11338 (85.4315, -86.1738) -> (85.6222, -85.6215)
  line L11339 (99.9903, -95.7008) -> (99.5358, -96.0681)
  line L11340 (37.0211, -112.987) -> (37.0318, -112.55)
  line L11341 (90.2951, -80.628) -> (90.8336, -80.4011)
  line L11342 (94.2663, -79.802) -> (94.8498, -79.8331)
  line L11343 (103.021, -89.2874) -> (103.032, -88.85)
  line L11344 (102.953, -87.6656) -> (102.855, -87.08)
  line L11345 (103.127, -88.85) -> (103.125, -89.0237)
  line L11346 (36.9531, -111.366) -> (36.8551, -110.78)
  line L11347 (85.0612, -89.6388) -> (85.0291, -89.0553)
  line L11348 (100.342, -82.4519) -> (99.9045, -82.0507)
  line L11349 (85.3803, -90.9861) -> (85.541, -91.5577)
  line L11350 (86.17, -84.6459) -> (85.9088, -85.1791)
  line L11351 (90.8336, -80.4011) -> (91.3856, -80.2094)
  line L11352 (93.8893, -79.897) -> (93.2963, -79.9291)
  line L11353 (99.9045, -82.0507) -> (99.4411, -81.6795)
  line L11354 (22.8893, -105.251) -> (22.417, -105.61)
  line L11355 (88.643, -96.0871) -> (88.1873, -95.7214)
  line L11356 (101.199, -94.4342) -> (100.823, -94.8821)
  line L11357 (85.2769, -86.7373) -> (85.4315, -86.1738)
  line L11358 (107.277, -86.7373) -> (107.432, -86.1738)
  line L11359 (88.0847, -95.5049) -> (88.539, -95.8873)
  line L11360 (36.1527, -116.419) -> (36.3914, -115.876)
  line L11361 (35.8006, -108.018) -> (35.4833, -107.517)
  line L11362 (98.0441, -96.9841) -> (97.5109, -97.2231)
  line L11363 (85.8482, -85.0827) -> (86.1085, -84.5595)
  line L11364 (85.7774, -92.4587) -> (85.5618, -91.9156)
  line L11365 (94.0455, -97.8049) -> (94.6391, -97.7873)
  line L11366 (35.1334, -107.037) -> (34.7525, -106.581)
  line L11367 (102.781, -91.3293) -> (102.602, -91.8858)
  line L11368 (22.417, -105.61) -> (21.9695, -106.001)
  line L11369 (100.856, -94.7014) -> (101.229, -94.2393)
  line L11370 (85.6222, -85.6215) -> (85.8482, -85.0827)
  line L11371 (120.199, -80.7936) -> (120.711, -81.0764)
  line L11372 (85.2321, -87.4491) -> (85.1587, -88.0384)
  line L11373 (109.084, -83.1057) -> (109.469, -82.6664)
  line L11374 (101.858, -93.4704) -> (101.544, -93.963)
  line L11375 (96.2432, -80.161) -> (95.6626, -80.0365)
  line L11376 (108.402, -84.0542) -> (108.727, -83.569)
  line L11377 (110.32, -81.8668) -> (110.783, -81.5099)
  line L11378 (21.157, -106.866) -> (20.7955, -107.337)
  line L11379 (26.7068, -103.7) -> (26.1233, -103.811)
  line L11380 (36.5935, -115.317) -> (36.7582, -114.747)
  line L11381 (89.6204, -96.7267) -> (89.1214, -96.4227)
  line L11382 (89.2676, -81.1835) -> (89.7724, -80.8892)
  line L11383 (102.855, -87.08) -> (102.719, -86.5021)
  line L11384 (33.9045, -105.751) -> (33.4411, -105.379)
  line L11385 (113.386, -80.2094) -> (113.949, -80.0538)
  line L11386 (100.543, -82.518) -> (100.938, -82.9485)
  line L11387 (19.6834, -109.429) -> (19.495, -109.992)
  line L11388 (97.9179, -80.7606) -> (97.3734, -80.5239)
  line L11389 (93.682, -79.8086) -> (94.2663, -79.802)
  line L11390 (108.108, -84.5595) -> (108.402, -84.0542)
  line L11391 (125.051, -87.6844) -> (125.108, -88.266)
  line L11392 (102.456, -85.4305) -> (102.659, -85.9784)
  line L11393 (100.823, -94.8821) -> (100.42, -95.3049)
  line L11394 (24.4345, -104.369) -> (23.9003, -104.629)
  line L11395 (103.012, -88.2565) -> (102.953, -87.6656)
  line L11396 (92.35, -97.7337) -> (91.7803, -97.6038)
  line L11397 (99.4411, -81.6795) -> (98.954, -81.3397)
  line L11398 (89.7724, -80.8892) -> (90.2951, -80.628)
  line L11399 (87.7561, -95.327) -> (87.3513, -94.9056)
  line L11400 (99.0844, -96.274) -> (99.5654, -95.9258)
  line L11401 (117.43, -79.9018) -> (118.005, -80.0077)
  line L11402 (100.42, -95.3049) -> (99.9903, -95.7008)
  line L11403 (87.6569, -95.0931) -> (88.0847, -95.5049)
  line L11404 (96.4039, -97.5957) -> (95.8346, -97.7276)
  line L11405 (98.5607, -96.7111) -> (98.0441, -96.9841)
  line L11406 (37.0318, -112.55) -> (37.0121, -111.957)
  line L11407 (125.125, -89.0237) -> (125.095, -89.6073)
  line L11408 (85.078, -87.8883) -> (85.1589, -87.3096)
  line L11409 (85.3817, -91.3597) -> (85.2379, -90.7934)
  line L11410 (102.602, -91.8858) -> (102.389, -92.4297)
  line L11411 (93.4521, -97.7832) -> (94.0455, -97.8049)
  line L11412 (19.232, -111.149) -> (19.1587, -111.738)
  line L11413 (99.5654, -95.9258) -> (100.022, -95.5465)
  line L11414 (118.005, -80.0077) -> (118.571, -80.1506)
  line L11415 (111.268, -81.1835) -> (111.772, -80.8892)
  line L11416 (85.541, -91.5577) -> (85.7392, -92.1175)
  line L11417 (97.5182, -97.1173) -> (98.0585, -96.8711)
  line L11418 (32.954, -105.04) -> (32.4456, -104.733)
  line L11419 (89.9003, -80.9286) -> (89.3845, -81.2228)
  line L11420 (19.9088, -108.879) -> (19.6834, -109.429)
  line L11421 (90.9847, -80.4458) -> (90.4345, -80.6692)
  line L11422 (85.0332, -88.6312) -> (85.0347, -88.471)
  line L11423 (96.3945, -97.4999) -> (96.9627, -97.3272)
  line L11424 (85.9088, -85.1791) -> (85.6834, -85.7285)
  line L11425 (19.3443, -110.566) -> (19.232, -111.149)
  line L11426 (124.957, -87.1077) -> (125.051, -87.6844)
  line L11427 (110.783, -81.5099) -> (111.268, -81.1835)
  line L11428 (89.3845, -81.2228) -> (88.8893, -81.5505)
  line L11429 (86.466, -84.1311) -> (86.17, -84.6459)
  line L11430 (96.9634, -97.4273) -> (96.4039, -97.5957)
  line L11431 (125.127, -88.85) -> (125.125, -89.0237)
  line L11432 (101.229, -94.2393) -> (101.57, -93.7534)
  line L11433 (26.1233, -103.811) -> (25.5484, -103.959)
  line L11434 (20.17, -108.346) -> (19.9088, -108.879)
  line L11435 (108.727, -83.569) -> (109.084, -83.1057)
  line L11436 (97.671, -80.5443) -> (98.1995, -80.7936)
  line L11437 (116.266, -79.802) -> (116.85, -79.8331)
  line L11438 (19.495, -109.992) -> (19.3443, -110.566)
  line L11439 (116.85, -79.8331) -> (117.43, -79.9018)
  line L11440 (91.3856, -80.2094) -> (91.9488, -80.0538)
  line L11441 (85.1245, -88.6312) -> (85.1297, -89.225)
  line L11442 (95.6626, -80.0365) -> (95.075, -79.9508)
  line L11443 (91.1318, -97.3069) -> (91.6987, -97.4835)
  line L11444 (33.4411, -105.379) -> (32.954, -105.04)
  line L11445 (109.882, -82.2528) -> (110.32, -81.8668)
  line L11446 (87.0836, -106.806) -> (87.4688, -106.366)
  line L11447 (94.6391, -121.487) -> (95.2302, -121.43)
  line L11448 (86.7274, -107.269) -> (87.0836, -106.806)
  line L11449 (41.1587, -111.738) -> (41.1245, -112.331)
  line L11450 (43.9695, -106.001) -> (43.5489, -106.42)
  line L11451 (91.9488, -103.754) -> (92.5208, -103.635)
  line L11452 (96.5713, -103.851) -> (97.1275, -104.03)
  line L11453 (102.391, -115.876) -> (102.594, -115.317)
  line L11454 (97.671, -104.244) -> (98.1995, -104.494)
  line L11455 (86.1085, -108.26) -> (86.402, -107.754)
  line L11456 (174.108, -108.26) -> (174.402, -107.754)
  line L11457 (102.153, -116.419) -> (102.391, -115.876)
  line L11458 (173.078, -111.588) -> (173.159, -111.01)
  line L11459 (90.2951, -104.328) -> (90.8336, -104.101)
  line L11460 (89.7724, -104.589) -> (90.2951, -104.328)
  line L11461 (100.453, -118.838) -> (100.856, -118.401)
  line L11462 (86.402, -107.754) -> (86.7274, -107.269)
  line L11463 (102.953, -111.366) -> (102.855, -110.78)
  line L11464 (95.2302, -121.43) -> (95.8162, -121.334)
  line L11465 (96.0047, -103.708) -> (96.5713, -103.851)
  line L11466 (95.4301, -103.602) -> (96.0047, -103.708)
  line L11467 (174.402, -107.754) -> (174.727, -107.269)
  line L11468 (102.594, -115.317) -> (102.758, -114.747)
  line L11469 (91.6987, -121.183) -> (92.2761, -121.322)
  line L11470 (101.641, -107.581) -> (101.946, -108.08)
  line L11471 (103.095, -113.307) -> (103.027, -113.888)
  line L11472 (103.027, -113.888) -> (102.922, -114.462)
  line L11473 (102.922, -114.462) -> (102.781, -115.029)
  line L11474 (100.543, -106.218) -> (100.938, -106.649)
  line L11475 (100.938, -106.649) -> (101.304, -107.104)
  line L11476 (100.342, -106.152) -> (99.9045, -105.751)
  line L11477 (167.801, -108.018) -> (167.483, -107.517)
  line L11478 (92.8615, -121.422) -> (93.4521, -121.483)
  line L11479 (102.14, -116.659) -> (101.858, -117.17)
  line L11480 (56.7525, -106.581) -> (56.3423, -106.152)
  line L11481 (85.1309, -113.919) -> (85.0612, -113.339)
  line L11482 (57.4833, -107.517) -> (57.1334, -107.037)
  line L11483 (85.0291, -112.755) -> (85.0332, -112.331)
  line L11484 (52.3945, -121.2) -> (52.9627, -121.027)
  line L11485 (85.541, -115.258) -> (85.7392, -115.817)
  line L11486 (41.0347, -112.171) -> (41.078, -111.588)
  line L11487 (43.7561, -119.027) -> (43.3513, -118.606)
  line L11488 (44.643, -119.787) -> (44.1873, -119.421)
  line L11489 (85.3817, -115.06) -> (85.2379, -114.493)
  line L11490 (43.3513, -118.606) -> (42.9746, -118.159)
  line L11491 (85.7774, -116.159) -> (85.5618, -115.616)
  line L11492 (58.3887, -116.13) -> (58.1404, -116.659)
  line L11493 (56.9379, -106.649) -> (57.3045, -107.104)
  line L11494 (181.682, -103.509) -> (182.266, -103.502)
  line L11495 (42.1085, -108.26) -> (42.402, -107.754)
  line L11496 (49.682, -103.509) -> (50.2663, -103.502)
  line L11497 (85.1587, -111.738) -> (85.1245, -112.331)
  line L11498 (181.099, -103.553) -> (181.682, -103.509)
  line L11499 (180.521, -103.635) -> (181.099, -103.553)
  line L11500 (168.855, -110.78) -> (168.719, -110.202)
  line L11501 (166.753, -106.581) -> (166.342, -106.152)
  line L11502 (50.483, -103.604) -> (49.8893, -103.597)
  line L11503 (166.856, -118.401) -> (167.229, -117.939)
  line L11504 (49.0994, -103.553) -> (49.682, -103.509)
  line L11505 (85.6834, -109.429) -> (85.495, -109.992)
  line L11506 (102.885, -114.167) -> (102.972, -113.579)
  line L11507 (85.9741, -116.363) -> (86.2446, -116.891)
  line L11508 (93.0994, -103.553) -> (93.682, -103.509)
  line L11509 (89.0175, -119.939) -> (89.5183, -120.258)
  line L11510 (41.6834, -109.429) -> (41.495, -109.992)
  line L11511 (98.7108, -104.776) -> (99.2028, -105.092)
  line L11512 (99.2028, -105.092) -> (99.6734, -105.438)
  line L11513 (102.218, -108.597) -> (102.456, -109.131)
  line L11514 (159.296, -103.629) -> (158.707, -103.7)
  line L11515 (103.125, -112.724) -> (103.095, -113.307)
  line L11516 (151.159, -111.738) -> (151.124, -112.331)
  line L11517 (57.6409, -107.581) -> (57.9457, -108.08)
  line L11518 (102.827, -110.238) -> (102.957, -110.808)
  line L11519 (101.544, -117.663) -> (101.199, -118.134)
  line L11520 (101.858, -117.17) -> (101.544, -117.663)
  line L11521 (93.4521, -121.483) -> (94.0455, -121.505)
  line L11522 (49.8893, -103.597) -> (49.2963, -103.629)
  line L11523 (42.7955, -107.337) -> (42.466, -107.831)
  line L11524 (49.2963, -103.629) -> (48.7068, -103.7)
  line L11525 (43.157, -106.866) -> (42.7955, -107.337)
  line L11526 (43.5489, -106.42) -> (43.157, -106.866)
  line L11527 (86.2446, -116.891) -> (86.5495, -117.401)
  line L11528 (103.012, -111.957) -> (102.953, -111.366)
  line L11529 (54.954, -105.04) -> (54.4456, -104.733)
  line L11530 (55.4411, -105.379) -> (54.954, -105.04)
  line L11531 (161.075, -103.651) -> (160.483, -103.604)
  line L11532 (47.5484, -103.959) -> (46.9847, -104.146)
  line L11533 (48.1233, -103.811) -> (47.5484, -103.959)
  line L11534 (48.7068, -103.7) -> (48.1233, -103.811)
  line L11535 (174.727, -107.269) -> (175.084, -106.806)
  line L11536 (175.084, -106.806) -> (175.469, -106.366)
  line L11537 (85.7392, -115.817) -> (85.9741, -116.363)
  line L11538 (58.5439, -109.635) -> (58.3321, -109.08)
  line L11539 (58.4559, -109.131) -> (58.6591, -109.678)
  line L11540 (169.032, -112.55) -> (169.012, -111.957)
  line L11541 (94.0455, -121.505) -> (94.6391, -121.487)
  line L11542 (175.882, -105.953) -> (176.32, -105.567)
  line L11543 (51.2581, -121.523) -> (50.6766, -121.58)
  line L11544 (151.124, -112.331) -> (151.13, -112.925)
  line L11545 (56.3423, -106.152) -> (55.9045, -105.751)
  line L11546 (163.918, -104.461) -> (163.373, -104.224)
  line L11547 (55.9045, -105.751) -> (55.4411, -105.379)
  line L11548 (89.6204, -120.427) -> (89.1214, -120.123)
  line L11549 (52.8143, -104.024) -> (52.2432, -103.861)
  line L11550 (97.5182, -120.817) -> (98.0585, -120.571)
  line L11551 (101.946, -108.08) -> (102.218, -108.597)
  line L11552 (52.2432, -103.861) -> (51.6626, -103.737)
  line L11553 (85.8482, -108.783) -> (86.1085, -108.26)
  line L11554 (91.3856, -103.909) -> (91.9488, -103.754)
  line L11555 (101.304, -107.104) -> (101.641, -107.581)
  line L11556 (101.57, -117.453) -> (101.879, -116.946)
  line L11557 (41.0332, -112.331) -> (41.0347, -112.171)
  line L11558 (53.3734, -104.224) -> (52.8143, -104.024)
  line L11559 (53.9179, -104.461) -> (53.3734, -104.224)
  line L11560 (58.7185, -110.202) -> (58.5439, -109.635)
  line L11561 (54.4456, -104.733) -> (53.9179, -104.461)
  line L11562 (90.5778, -120.793) -> (91.1318, -121.007)
  line L11563 (88.539, -119.587) -> (89.0175, -119.939)
  line L11564 (86.8876, -117.889) -> (87.2572, -118.354)
  line L11565 (41.2321, -111.149) -> (41.1587, -111.738)
  line L11566 (97.1275, -104.03) -> (97.671, -104.244)
  line L11567 (100.022, -119.247) -> (100.453, -118.838)
  line L11568 (97.5109, -120.923) -> (96.9634, -121.127)
  line L11569 (41.3443, -110.566) -> (41.2321, -111.149)
  line L11570 (57.2286, -117.939) -> (57.57, -117.453)
  line L11571 (56.8557, -118.401) -> (57.2286, -117.939)
  line L11572 (58.1527, -116.419) -> (58.3914, -115.876)
  line L11573 (151.909, -108.879) -> (151.683, -109.429)
  line L11574 (164.446, -104.733) -> (163.918, -104.461)
  line L11575 (57.57, -117.453) -> (57.8785, -116.946)
  line L11576 (176.32, -105.567) -> (176.783, -105.21)
  line L11577 (85.3803, -114.686) -> (85.541, -115.258)
  line L11578 (98.954, -105.04) -> (98.4456, -104.733)
  line L11579 (45.5183, -120.258) -> (46.0392, -120.543)
  line L11580 (168.153, -116.419) -> (168.391, -115.876)
  line L11581 (41.1309, -113.919) -> (41.0612, -113.339)
  line L11582 (51.8346, -121.428) -> (51.2581, -121.523)
  line L11583 (91.1318, -121.007) -> (91.6987, -121.183)
  line L11584 (45.1214, -120.123) -> (44.643, -119.787)
  line L11585 (41.9741, -116.363) -> (42.2446, -116.891)
  line L11586 (89.3845, -104.923) -> (88.8893, -105.251)
  line L11587 (42.2446, -116.891) -> (42.5495, -117.401)
  line L11588 (167.879, -116.946) -> (168.153, -116.419)
  line L11589 (151.13, -112.925) -> (151.174, -113.517)
  line L11590 (57.3045, -107.104) -> (57.6409, -107.581)
  line L11591 (173.432, -109.874) -> (173.622, -109.322)
  line L11592 (56.42, -119.005) -> (55.9903, -119.401)
  line L11593 (169.021, -112.987) -> (169.032, -112.55)
  line L11594 (58.6024, -115.586) -> (58.3887, -116.13)
  line L11595 (86.466, -107.831) -> (86.17, -108.346)
  line L11596 (102.332, -109.08) -> (102.084, -108.54)
  line L11597 (95.8162, -121.334) -> (96.3945, -121.2)
  line L11598 (102.084, -108.54) -> (101.801, -108.018)
  line L11599 (44.417, -105.61) -> (43.9695, -106.001)
  line L11600 (86.6274, -117.689) -> (86.3113, -117.198)
  line L11601 (94.483, -103.604) -> (93.8893, -103.597)
  line L11602 (41.5618, -115.616) -> (41.3817, -115.06)
  line L11603 (178.834, -104.101) -> (179.386, -103.909)
  line L11604 (87.6569, -118.793) -> (88.0847, -119.205)
  line L11605 (89.5183, -120.258) -> (90.0392, -120.543)
  line L11606 (91.5484, -103.959) -> (90.9847, -104.146)
  line L11607 (92.2761, -121.322) -> (92.8615, -121.422)
  line L11608 (44.1873, -119.421) -> (43.7561, -119.027)
  line L11609 (51.6626, -103.737) -> (51.075, -103.651)
  line L11610 (42.3113, -117.198) -> (42.0276, -116.687)
  line L11611 (58.6591, -109.678) -> (58.8266, -110.238)
  line L11612 (185.671, -104.244) -> (186.199, -104.494)
  line L11613 (96.3945, -121.2) -> (96.9627, -121.027)
  line L11614 (45.2676, -104.884) -> (45.7724, -104.589)
  line L11615 (53.1275, -104.03) -> (53.671, -104.244)
  line L11616 (52.5713, -103.851) -> (53.1275, -104.03)
  line L11617 (173.622, -109.322) -> (173.848, -108.783)
  line L11618 (185.128, -104.03) -> (185.671, -104.244)
  line L11619 (43.4688, -106.366) -> (43.8816, -105.953)
  line L11620 (99.6734, -105.438) -> (100.121, -105.814)
  line L11621 (98.0585, -120.571) -> (98.5813, -120.29)
  line L11622 (50.6766, -121.58) -> (50.0926, -121.6)
  line L11623 (85.9088, -108.879) -> (85.6834, -109.429)
  line L11624 (182.266, -103.502) -> (182.85, -103.533)
  line L11625 (95.2581, -121.523) -> (94.6766, -121.58)
  line L11626 (41.495, -109.992) -> (41.3443, -110.566)
  line L11627 (88.8893, -105.251) -> (88.417, -105.61)
  line L11628 (97.9179, -104.461) -> (97.3734, -104.224)
  line L11629 (54.1995, -104.494) -> (54.7108, -104.776)
  line L11630 (42.6274, -117.689) -> (42.3113, -117.198)
  line L11631 (55.5358, -119.768) -> (55.0587, -120.105)
  line L11632 (155.385, -104.923) -> (154.889, -105.251)
  line L11633 (52.0047, -103.708) -> (52.5713, -103.851)
  line L11634 (56.8234, -118.582) -> (56.42, -119.005)
  line L11635 (166.022, -119.247) -> (166.453, -118.838)
  line L11636 (168.391, -115.876) -> (168.594, -115.317)
  line L11637 (103.051, -111.384) -> (103.108, -111.966)
  line L11638 (42.8876, -117.889) -> (43.2572, -118.354)
  line L11639 (103.127, -112.55) -> (103.125, -112.724)
  line L11640 (99.0844, -119.974) -> (99.5654, -119.626)
  line L11641 (85.1245, -112.331) -> (85.1297, -112.925)
  line L11642 (41.9088, -108.879) -> (41.6834, -109.429)
  line L11643 (101.229, -117.939) -> (101.57, -117.453)
  line L11644 (46.4345, -104.369) -> (45.9003, -104.629)
  line L11645 (168.332, -109.08) -> (168.084, -108.54)
  line L11646 (42.7274, -107.269) -> (43.0836, -106.806)
  line L11647 (99.5358, -119.768) -> (99.0587, -120.105)
  line L11648 (101.801, -108.018) -> (101.483, -107.517)
  line L11649 (96.2432, -103.861) -> (95.6626, -103.737)
  line L11650 (93.5085, -121.582) -> (92.9269, -121.527)
  line L11651 (85.1589, -111.01) -> (85.2769, -110.437)
  line L11652 (152.17, -108.346) -> (151.909, -108.879)
  line L11653 (95.6626, -103.737) -> (95.075, -103.651)
  line L11654 (87.3513, -118.606) -> (86.9746, -118.159)
  line L11655 (100.753, -106.581) -> (100.342, -106.152)
  line L11656 (158.707, -103.7) -> (158.123, -103.811)
  line L11657 (169.012, -111.957) -> (168.953, -111.366)
  line L11658 (87.9695, -106.001) -> (87.5489, -106.42)
  line L11659 (59.0318, -112.55) -> (59.0121, -111.957)
  line L11660 (176.783, -105.21) -> (177.268, -104.884)
  line L11661 (59.0211, -112.987) -> (59.0318, -112.55)
  line L11662 (98.1995, -104.494) -> (98.7108, -104.776)
  line L11663 (151.495, -109.992) -> (151.344, -110.566)
  line L11664 (102.389, -116.13) -> (102.14, -116.659)
  line L11665 (102.957, -110.808) -> (103.051, -111.384)
  line L11666 (151.344, -110.566) -> (151.232, -111.149)
  line L11667 (85.495, -109.992) -> (85.3443, -110.566)
  line L11668 (94.8498, -103.533) -> (95.4301, -103.602)
  line L11669 (85.0347, -112.171) -> (85.078, -111.588)
  line L11670 (184.005, -103.708) -> (184.571, -103.851)
  line L11671 (98.5813, -120.29) -> (99.0844, -119.974)
  line L11672 (53.5109, -120.923) -> (52.9634, -121.127)
  line L11673 (168.544, -109.635) -> (168.332, -109.08)
  line L11674 (45.7724, -104.589) -> (46.2951, -104.328)
  line L11675 (55.9903, -119.401) -> (55.5358, -119.768)